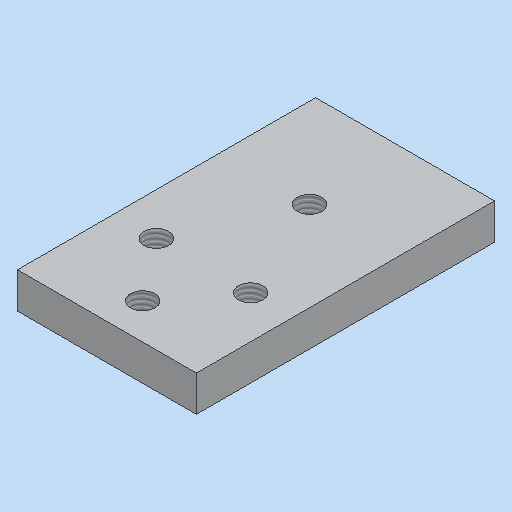
# Autodesk Inventor part: MM0937AN200_G04_220
Saved by Autodesk Inventor 2023.3 (Build 273359000, 359)
## iProperties
RuleStatus: InUse
Created: 2021-05-06
Part Number: MM0937AN200_G04_220
Material: 3.1645 AlCu4PbMgMn - AW 2007
Description: =<RBPARTNOTITLE2>
Document SubType Name: Modeling
Designer: frt9bw
Mass: 24.7319 g
Surface Area: 41.6432 cm^2
Volume: 8.67786 cm^3
Density: 2.85 g/cm^3
Appearance: Aluminium AnP
Vendor: ASW
AnP_Kategorie: 1
AnP_Material: =<Material>
MaxAbmaße: 10 x 40 x 30 (FM)
AnP_TemplVers: 20200821
RBDOCUMENTTYPE: DRF
RBDOCUMENTVERSION: 00
RBDRAWINGMAINSCALE: 1:1
RBDRAWINGMISSINGSPEC: --
RBDRAWINGVOLUME: --
RBDSV1: 0850
RBGBEDGESIN1: +0,5
RBGBEDGESIN2: +0,2
RBGBEDGESOUT1: -0,3
RBGBEDGESOUT2: -0,1
RBMATERIAL: =<Material>
RBMATMEETS: --
RBMATNO: =<Part Number>
RBPARTMADEOF: 10 x 40 x 30 (FM)
RBPARTNO: SIEHE MNR
RBPARTNOTITLE1: manufactured part
RBPARTNOTITLE2: Anfertigungsteil
RBPARTSAFETYINDICATOR: --
RBSURFACE: --
RBSURFACE2: --
RBZEDGESNORM: ISO13715:2002-06
RBZGENDIMCLASS: m
RBZGENDIMNORM: ISO 2768-1:1989-11
RBZGENGEOCLASS: H
RBZGENGEONORM: ISO 2768-2:1989-11
RBZSURFACENORM: ISO13D2:2002-02
RBZTOLERANCENORM: ISO 14405-1:2010-12
Author: frt9bw
Keywords: =<RBPARTMADEOF>
Comments: =<RBSURFACE2>
Revision Number: 01
Autodesk Inventor part; units mm, degrees
ref_plane "YZ Plane" through (0, 0, 0) normal (1, 0, 0) x (0, 1, 0)
ref_plane "XZ Plane" through (0, 0, 0) normal (0, 1, 0) x (-1, 0, 0)
ref_plane "XY Plane" through (0, 0, 0) normal (0, 0, 1) x (1, 0, 0)
sketch "Skizze1" plane through (0, 0, 0) normal (0, 0, 1) x (1, 0, 0)
  line L0 (0, 0) -> (30, 0)
  line L1 (30, 0) -> (30, 50)
  line L2 (30, 50) -> (0, 50)
  line L3 (0, 50) -> (0, 0)
  dimension "d0" = 30
  dimension "d1" = 50
  constraints: 8 end point, 2 parallel, 1 horizontal, 1 perpendicular
  measures "d0" distance of L2.end L1.end
  measures "d1" distance of L1.end L0.end
extrude "Extrusion1" add sketch "Skizze1" along normal blind 6
sketch "Skizze2" plane through (0, 0, 6) normal (0, 0, 1) x (1, 0, 0)
  line L0 (0, 50) -> (0, 0) projected
  line L1 (0, 0) -> (30, 0) projected
  line L2 (30, 50) -> (0, 50) projected
  point P0 (15, 6)
  point P1 (15, 34)
  dimension "d4" = 15
  dimension "d5" = 28
  dimension "d6" = 50
  dimension "d7" = 16
  constraints: 1 vertical alignment
  measures "d4" distance from line of point (15, 6) L0
  measures "d5" distance of point (15, 6) point (15, 34)
  measures "d6" distance between parallel lines of L1 L2
  measures "d7" distance from line of L2 point (15, 34)
hole "Bohrung1" at (15, 6, 6) at (15, 34, 6) direction (0, 0, -1) diameter 4.134 depth 14.2 tip angle 118 thread size "M5x0.8" designation "M5" class "6H" standard "ISO Metric profile"
sketch "Skizze3" plane through (0, 0, 6) normal (0, 0, 1) x (1, 0, 0)
  line L0 (0, 50) -> (0, 0) projected
  line L1 (0, 0) -> (30, 0) projected
  point P0 (7.1, 16.2)
  point P1 (22.9, 16.2)
  dimension "d15" = 15.8
  dimension "d16" = 7.1
  dimension "d17" = 16.2
  constraints: 1 horizontal alignment
  measures "d15" distance of point (22.9, 16.2) point (7.1, 16.2)
  measures "d16" distance from line of point (7.1, 16.2) L0
  measures "d17" distance from line of point (7.1, 16.2) L1
hole "Bohrung2" at (7.1, 16.2, 6) at (22.9, 16.2, 6) direction (0, 0, -1) diameter 4.134 end through all thread size "M5x0.8" designation "M5" class "6H" standard "ISO Metric profile"
